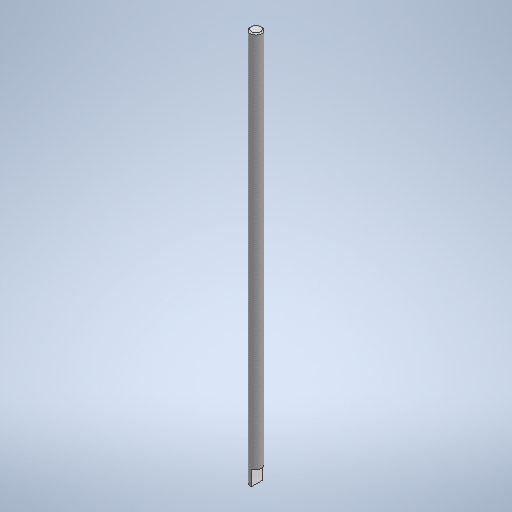
# Autodesk Inventor part: popychacz
Saved by Autodesk Inventor 2025.2 (Build 292293000, 293)
## iProperties
Created: 2025-04-06
Part Number: popychacz
Material: Generic
Document SubType Name: Modeling
Designer: makst
Density: 1 g/cm^3
Appearance: Default
Author: makst
Autodesk Inventor part; units mm, degrees
ref_plane "YZ Plane" through (0, 0, 0) normal (1, 0, 0) x (0, 1, 0)
ref_plane "XZ Plane" through (0, 0, 0) normal (0, 1, 0) x (-1, 0, 0)
ref_plane "XY Plane" through (0, 0, 0) normal (0, 0, 1) x (1, 0, 0)
sketch "Sketch1" plane through (0, 0, 0) normal (0, 1, 0) x (-1, 0, 0)
  circle A0 centre (0, 0) radius 2.5
  dimension "d0" = 5
  constraints: 1 centre point, 1 coincident
  measures "d0" diameter of A0
extrude "Extrusion1" add sketch "Sketch1" along normal blind 175
thread "Thread3" size "M5x0.8" class "6g" standard "ANSI Metric M Profile" length 189.5
chamfer "Chamfer5" distance 0.5 angle 45 1 edges at (2.5, 175, 0)
sketch "Sketch7" plane through (0, 0, 0) normal (0, -1, 0) x (1, 0, 0)
  circle A0 centre (0, 0) radius 2.0919
  line L0 (0, 2.0919) -> (0, -2.0919)
  line L1 (0.5, 0) -> (0.5, 2.4495)
  circle A1 centre (0, 0) radius 2.5 projected
  line L2 (0.5, 0) -> (0.5, -2.4495)
  dimension "d63" = 0.5
  constraints: 6 end point, 4 point on circle, 3 vertical, 1 centre point, 1 coincident, 1 midpoint
  measures "d63" distance of L1.start point (0, 0)
extrude "Extrusion2" cut sketch "Sketch7" against normal blind 6.8 contours L1 A1 L2 A0 | A0 L2 L1 picked at (2.3253, -0.3418)
body "Solid1"
